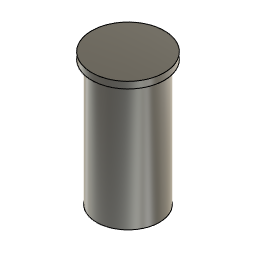
X-Laser (Autodesk Fusion 360 archive; units mm, degrees)
design "19MM自锁按钮"
Autodesk Fusion 360 part; units mm, degrees
sketch "草图1" plane through (0, 0, 0) normal (0, 0, 1) x (1, 0, 0)
  circle A0 centre (0, 0) radius 9.5
  dimension "d1" = 19
  constraint coincident A0.centre origin
  measures "d1" diameter of A0
extrude "拉伸1" add sketch "草图1" along normal blind 45
sketch "草图2" plane through (0, 0, 45) normal (0, 0, 1) x (-1, 0, 0)
  circle A0 centre (0, 0) radius 9.5
  circle A1 centre (0, 0) radius 11
  dimension "d4" = 22
  constraint coincident A0.centre A1.centre
  measures "d4" diameter of A1
extrude "拉伸2" add sketch "草图2" against normal blind 2
move_face "偏移面1" offset -5 1 faces at (1.5221, 2.3363, 0)
sketch "草图3" plane through (0, 0, 45) normal (0, 0, 1) x (-1, 0, 0)
  circle A0 centre (0, 0) radius 11
  circle A1 centre (0, 0) radius 9.5
  dimension "d7" = 19
  constraint coincident A0.centre A1.centre
  measures "d7" diameter of A1

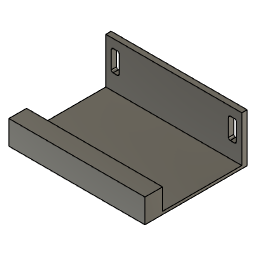
design "振镜驱动板 poor"
Autodesk Fusion 360 part; units mm, degrees
sketch "草图1" plane through (0, 0, 0) normal (0, 0, 1) x (1, 0, 0)
  line L0 (38.6, -29) -> (-38.6, -29)
  line L1 (-38.6, -29) -> (-38.6, 29)
  line L2 (-38.6, 29) -> (38.6, 29)
  line L3 (38.6, 29) -> (38.6, -29)
  line L4 (38.6, -29) -> (-38.6, 29) construction
  line L5 (-38.6, -29) -> (38.6, 29) construction
  line L6 (-38.6, 26) -> (38.6, 26)
  line L7 (-38.6, -19) -> (38.6, -19)
  dimension "d1" = 58
  dimension "d2" = 77.2
  dimension "d3" = 3
  dimension "d4" = 10
  constraint horizontal L0
  constraint perpendicular L0 L1
  constraint parallel L0 L2
  constraint parallel L1 L3
  constraint coincident L4 origin
  constraint coincident L5 origin
  constraint perpendicular L1 L6
  constraint coincident L1 L6.start
  constraint coincident L3 L6.end
  constraint perpendicular L3 L7
  constraint coincident L1 L7.start
  constraint coincident L3 L7.end
  measures "d1" distance of L0.end L1.end
  measures "d2" distance of L1.end L2.end
  measures "d3" distance of L2 L6
  measures "d4" distance of L0 L7
extrude "拉伸1" add sketch "草图1" against normal blind 1.6
extrude "拉伸2" add sketch "草图1" along normal blind 12 contours L0 L1 L3 L7
extrude "拉伸3" add sketch "草图1" along normal blind 25.9 contours L1 L2 L3 L6
sketch "草图2" plane through (0, 29, 0) normal (0, 1, 0) x (-1, 0, 0)
  line L0 (-38.6, 25.9) -> (-38.6, -1.6)
  line L1 (-38.6, -1.6) -> (38.6, -1.6)
  line L2 (38.6, -1.6) -> (38.6, 25.9)
  line L3 (38.6, 25.9) -> (-38.6, 25.9)
  line L4 (-32, 9) -> (-34.5, 9)
  line L5 (-35.5, 10) -> (-35.5, 20)
  line L6 (-34.5, 21) -> (-32, 21)
  line L7 (-31, 20) -> (-31, 10)
  line L8 (-31, 9) -> (-35.5, 21) construction
  line L9 (-35.5, 9) -> (-31, 21) construction
  arc A0 (-34.5, 21) -> (-35.5, 20) centre (-34.5, 20) ccw
  arc A1 (-31, 20) -> (-32, 21) centre (-32, 20) ccw
  arc A2 (-35.5, 10) -> (-34.5, 9) centre (-34.5, 10) ccw
  arc A3 (-32, 9) -> (-31, 10) centre (-32, 10) ccw
  line L10 (0, 31) -> (0, -9) construction
  line L11 (0, 31) -> (0, -9) construction
  line L12 (31, 9) -> (35.5, 21) construction
  arc A4 (35.5, 20) -> (34.5, 21) centre (34.5, 20) ccw
  line L13 (34.5, 21) -> (32, 21)
  line L14 (32, 9) -> (34.5, 9)
  line L15 (31, 20) -> (31, 10)
  line L16 (35.5, 9) -> (31, 21) construction
  arc A5 (31, 10) -> (32, 9) centre (32, 10) ccw
  arc A6 (34.5, 9) -> (35.5, 10) centre (34.5, 10) ccw
  arc A7 (32, 21) -> (31, 20) centre (32, 20) ccw
  line L17 (35.5, 10) -> (35.5, 20)
  point P0 (-33.25, 15)
  point P1 (33.25, 15)
  dimension "d11" = 12
  dimension "d12" = 4.5
  dimension "d13" = 5.35
  dimension "d14" = 1
  dimension "d15" = 1
  dimension "d16" = 1
  dimension "d17" = 1
  constraint horizontal L4
  constraint perpendicular L4 L5
  constraint parallel L4 L6
  constraint parallel L5 L7
  constraint coincident L8 P0
  constraint coincident L9 P0
  constraint coincident L8.end L6
  constraint coincident L8.end L5
  constraint tangent L6 A0
  constraint tangent L5 A0
  constraint coincident L9.end L6
  constraint coincident L9.end L7
  constraint tangent L6 A1
  constraint tangent L7 A1
  constraint coincident L9.start L5
  constraint coincident L9.start L4
  constraint tangent L5 A2
  constraint tangent L4 A2
  constraint coincident L8.start L7
  constraint coincident L8.start L4
  constraint tangent L7 A3
  constraint tangent L4 A3
  constraint perpendicular L1 L10
  constraint symmetric L8.start L10 L12.start
  constraint symmetric L9.start L10 L16.start
  constraint symmetric L8.end L10 L12.end
  constraint symmetric L9.end L10 L16.end
  constraint symmetric P0 L10 P1
  constraint symmetric L6.start L10 A4.end
  constraint symmetric L5.end L10 A4.start
  constraint symmetric A0 L10 A4
  constraint symmetric L6.end L10 L13.end
  constraint symmetric L7.start L10 L15.start
  constraint symmetric A1 L10 A7
  constraint symmetric L5.start L10 A6.end
  constraint symmetric L4.end L10 L14.end
  constraint symmetric A2 L10 A6
  constraint symmetric L7.end L10 L15.end
  constraint symmetric L4.start L10 L14.start
  constraint symmetric A3 L10 A5
  constraint symmetric L11.start L10 L10.start
  constraint symmetric L11.end L10 L10.end
  measures "d11" distance of L9.start L8.end
  measures "d12" distance of L8.end L9.end
  measures "d13" distance of L0 P0
  measures "d14" radius of A0
  measures "d15" radius of A1
  measures "d16" radius of A2
  measures "d17" radius of A3
extrude "拉伸4" cut sketch "草图2" against normal blind 15 contours L4 L5 L6 L7 A0 A1 A2 A3 | A4 L13 L14 L15 A5 A6 A7 L17
